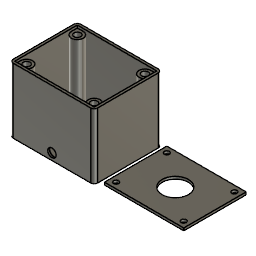
Single 16mm Button Box With Lid (Autodesk Fusion 360 design; units mm, degrees)
Autodesk Fusion 360 part; units mm, degrees
sketch "Sketch1" plane through (0, 0, 0) normal (0, 0, 1) x (1, 0, 0)
  line L0 (0, 0) -> (50, 0)
  line L1 (50, 0) -> (50, 40)
  line L2 (50, 40) -> (0, 40)
  line L3 (0, 40) -> (0, 0)
  dimension "d1" = 50
  dimension "d2" = 40
  constraint horizontal L0
  constraint vertical L1
  constraint horizontal L2
  constraint vertical L3
  constraint coincident L0.start L3.end
  measures "d1" distance of L0.start L0.end
  measures "d2" distance of L0.end L1.end
extrude "Extrude1" add sketch "Sketch1" along normal blind 1 makes body 1
sketch "Sketch2" plane through (0, 0, 1) normal (0, 0, 1) x (-1, 0, 0)
  line L0 (0, -40) -> (0, 0)
  line L1 (0, 0) -> (-50, 0)
  line L2 (-50, 0) -> (-50, -40)
  line L3 (-50, -40) -> (0, -40)
  line L4 (-1.5, -38.5) -> (-48.5, -38.5)
  line L5 (-48.5, -38.5) -> (-48.5, -1.5)
  line L6 (-48.5, -1.5) -> (-1.5, -1.5)
  line L7 (-1.5, -1.5) -> (-1.5, -38.5)
  dimension "d5" = 1.5
  dimension "d6" = 1.5
  dimension "d7" = 1.5
  dimension "d8" = 1.5
  constraint horizontal L4
  constraint vertical L5
  constraint horizontal L6
  constraint vertical L7
  measures "d5" distance of L2 L5
  measures "d6" distance of L3 L4
  measures "d7" distance of L0 L7
  measures "d8" distance of L1 L6
extrude "Extrude2" add sketch "Sketch2" along normal blind 37.5 bodies 1
sketch "Sketch3" plane through (0, 0, 0) normal (0, -1, 0) x (1, 0, 0)
  line L0 (0, 0) -> (50, 0)
  line L1 (50, 0) -> (50, 38.5)
  line L2 (50, 38.5) -> (0, 38.5)
  line L3 (0, 38.5) -> (0, 0)
  circle A0 centre (25, 4) radius 2.5
  dimension "d11" = 5
  dimension "d12" = 50
  dimension "d13" = 25
  dimension "d14" = 4
  measures "d11" diameter of A0
  measures "d12" distance of L0.start L0.end
  measures "d13" distance of L3 A0.centre
  measures "d14" distance of L0 A0.centre
extrude "Extrude3" cut sketch "Sketch3" against normal blind 1.6 contours A0 bodies 1
fillet "Fillet1" radius 0.5 1 edges at (22.6692, 1.5, 3.096) on bodies 1
sketch "Sketch4" plane through (0, 0, 1) normal (0, 0, 1) x (-1, 0, 0)
  line L0 (-48.5, -1.5) -> (-48.5, -38.5)
  line L1 (-48.5, -38.5) -> (-1.5, -38.5)
  line L2 (-1.5, -38.5) -> (-1.5, -1.5)
  line L3 (-1.5, -1.5) -> (-25, -1.5)
  line L4 (-25, -1.5) -> (-48.5, -1.5)
  circle A0 centre (-5, -35) radius 3.5
  circle A1 centre (-45, -35) radius 3.5
  circle A2 centre (-5, -5) radius 3.5
  circle A3 centre (-45, -5) radius 3.5
  dimension "d19" = 7
  dimension "d20" = 3.5
  dimension "d21" = 3.5
  dimension "d22" = 3.5
  dimension "d23" = 3.5
  dimension "d24" = 3.5
  dimension "d25" = 3.5
  dimension "d26" = 3.5
  dimension "d27" = 3.5
  constraint equal A0 A1
  constraint equal A1 A2
  constraint equal A2 A3
  measures "d19" diameter of A0
  measures "d20" distance of L1 A0.centre
  measures "d21" distance of L2 A0.centre
  measures "d22" distance of L1 A1.centre
  measures "d23" distance of L0 A1.centre
  measures "d24" distance of L4 A3.centre
  measures "d25" distance of L0 A3.centre
  measures "d26" distance of L2 A2.centre
  measures "d27" distance of L3 A2.centre
extrude "Extrude4" add sketch "Sketch4" along normal blind 36 contours L0 L4 A3 | A3 | L0 L1 A1 | A1 | L2 L3 A2 | A2 | L1 L2 A0 | A0 bodies 1
sketch "Sketch5" plane through (0, 0, 37) normal (0, 0, 1) x (-1, 0, 0)
  arc A0 (-45, -38.5) -> (-48.5, -35) centre (-45, -35) ccw
  line L0 (-48.5, -35) -> (-48.5, -38.5)
  line L1 (-48.5, -38.5) -> (-45, -38.5)
  circle A1 centre (-5, -5) radius 2
  circle A2 centre (-45, -5) radius 2
  circle A3 centre (-45, -35) radius 2
  circle A4 centre (-5, -35) radius 2
  dimension "d30" = 4
  constraint concentric A0 A3
  constraint equal A1 A2
  constraint equal A2 A3
  constraint equal A3 A4
  measures "d30" diameter of A1
extrude "Extrude5" cut sketch "Sketch5" against normal blind 10 contours A1 | A2 | A3 | A4 bodies 1
fillet "Fillet2" radius 2 4 edges at (50, 0, 19.25) (0, 0, 19.25) (0, 40, 19.25) (50, 40, 19.25) on bodies 1
sketch "Sketch6" plane through (0, 0, 0) normal (0, 0, 1) x (1, 0, 0)
  line L0 (53, 40) -> (100, 40)
  line L1 (100, 40) -> (100, 3)
  line L2 (100, 3) -> (53, 3)
  line L3 (53, 3) -> (53, 40)
  line L4 (1.5, 38.5) -> (48.5, 38.5)
  line L5 (1.5, 1.5) -> (1.5, 38.5)
  circle A0 centre (56.5, 36.5) radius 1.5
  circle A1 centre (96.5, 36.5) radius 1.5
  circle A2 centre (96.5, 6.5) radius 1.5
  circle A3 centre (56.5, 6.5) radius 1.5
  dimension "d35" = 47
  dimension "d36" = 37
  dimension "d37" = 47
  dimension "d38" = 37
  dimension "d39" = 3
  dimension "d40" = 3.5
  dimension "d41" = 3.5
  dimension "d42" = 3.5
  dimension "d43" = 3.5
  dimension "d44" = 3.5
  dimension "d45" = 3.5
  dimension "d46" = 3.5
  dimension "d47" = 3.5
  constraint horizontal L0
  constraint vertical L1
  constraint horizontal L2
  constraint vertical L3
  constraint equal A0 A1
  constraint equal A1 A2
  constraint equal A2 A3
  measures "d35" distance of L4.start L4.end
  measures "d36" distance of L4.start L5.start
  measures "d37" distance of L1.end L2.end
  measures "d38" distance of L0.end L1.end
  measures "d39" diameter of A0
  measures "d40" distance of L0 A0.centre
  measures "d41" distance of L3 A0.centre
  measures "d42" distance of L0 A1.centre
  measures "d43" distance of L1 A1.centre
  measures "d44" distance of L1 A2.centre
  measures "d45" distance of L2 A2.centre
  measures "d46" distance of L2 A3.centre
  measures "d47" distance of L3 A3.centre
extrude "Extrude6" add sketch "Sketch6" along normal blind 1.5 separate body makes body 2
sketch "Sketch7" plane through (0, 0, 1.5) normal (0, 0, 1) x (-1, 0, 0)
  circle A0 centre (-56.5, -6.5) radius 1.5
  circle A1 centre (-96.5, -6.5) radius 1.5
  circle A2 centre (-96.5, -36.5) radius 1.5
  circle A3 centre (-56.5, -36.5) radius 1.5
  line L0 (-53, -3) -> (-100, -3)
  line L1 (-100, -3) -> (-100, -40)
  line L2 (-100, -40) -> (-53, -40)
  line L3 (-53, -40) -> (-53, -3)
  circle A4 centre (-76.5, -21.5) radius 7.75
  dimension "d50" = 47
  dimension "d51" = 37
  dimension "d52" = 18.5
  dimension "d53" = 23.5
  dimension "d54" = 15.5
  measures "d50" distance of L0.start L0.end
  measures "d51" distance of L0.end L1.end
  measures "d52" distance of L0 A4.centre
  measures "d53" distance of L3 A4.centre
  measures "d54" diameter of A4
extrude "Extrude7" cut sketch "Sketch7" against normal blind 2 contours A4 bodies 2
chamfer "Chamfer1" distance 0.15 angle 45 4 edges at (100, 3, 0.75) (100, 40, 0.75) (53, 3, 0.75) (53, 40, 0.75) on bodies 2
equation "d52 = ( 37 / 2 ) * 1 mm"
equation "d53 = ( 47 / 2 ) * 1 mm"
named bodies: "16mmButtonBoxBase", "16mmButtonBoxLid"
